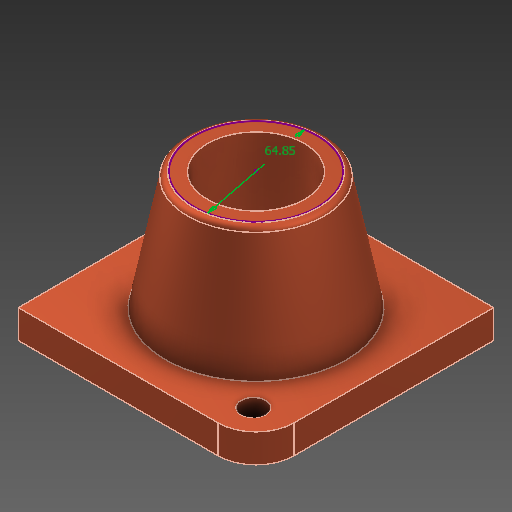
# Autodesk Inventor part: P FLange
Saved by Autodesk Inventor 2026.1 (Build 301233020, 233B)
## iProperties
Created: 2026-10-26
Part Number: P FLange
Material: Copper, Alloy
Document SubType Name: Modeling
Designer: YmCris
Density: 8.92 g/cm^3
Appearance: Copper - Satin
Author: YmCris
Autodesk Inventor part; units mm, degrees
ref_plane "YZ Plane" through (0, 0, 0) normal (1, 0, 0) x (0, 1, 0)
ref_plane "XZ Plane" through (0, 0, 0) normal (0, 1, 0) x (-1, 0, 0)
sketch "Sketch1" plane through (0, 0, 0) normal (0, 1, 0) x (-1, 0, 0)
  line L0 (62.5, 62.5) -> (-42.5, 62.5)
  line L1 (-62.5, 42.5) -> (-62.5, -62.5)
  line L2 (-62.5, -62.5) -> (42.5, -62.5)
  line L3 (62.5, -42.5) -> (62.5, 62.5)
  line L4 (62.5, 62.5) -> (-62.5, -62.5) construction
  line L5 (-62.5, 62.5) -> (62.5, -62.5) construction
  arc A0 (-42.5, 62.5) -> (-62.5, 42.5) centre (-42.5, 42.5) ccw
  arc A1 (42.5, -62.5) -> (62.5, -42.5) centre (42.5, -42.5) ccw
  point P0 (0, 0)
  dimension "d0" = 125
  dimension "d1" = 125
  dimension "d2" = 20
  dimension "d3" = 20
  constraints: 12 end point, 4 point on circle, 4 point on line, 4 tangent, 2 centre point, 2 midpoint, 2 parallel, 1 horizontal, 1 perpendicular
  measures "d0" distance of L5.end L1.end
  measures "d1" distance of L1.end L5.start
  measures "d2" radius of A0
  measures "d3" radius of A1
extrude "Extrusion1" add sketch "Sketch1" along normal blind 15
sketch "Sketch3" plane through (0, 15, 0) normal (0, 1, 0) x (1, 0, 0)
  point P0 (0, 0)
ref_plane "Work Plane1" through (0, 77, 0) normal (0, 1, 0) x (1, 0, 0)
sketch "Sketch4" plane through (0, 77, 0) normal (0, 1, 0) x (1, 0, 0)
  circle A0 centre (0, 0) radius 35.39
  dimension "d10" = 70.78
  constraints: 1 centre point, 1 coincident
  measures "d10" diameter of A0
sketch "Sketch5" plane through (0, 15, 0) normal (0, 1, 0) x (1, 0, 0)
  point P0 (0, 0)
sketch "Sketch6" plane through (0, 15, 0) normal (0, 1, 0) x (1, 0, 0)
  circle A0 centre (0, 0) radius 47.575
  dimension "d11" = 95.15
  constraints: 1 centre point, 1 coincident
  measures "d11" diameter of A0
loft "Loft1" add profiles "Sketch4", "Sketch6"
sketch "Sketch7" plane through (0, 77, 0) normal (0, 1, 0) x (1, 0, 0)
  circle A0 centre (0, 0) radius 25.5
  dimension "d16" = 51
  constraints: 1 centre point, 1 coincident
  measures "d16" diameter of A0
sketch "Sketch8" plane through (0, 77, 0) normal (0, 1, 0) x (1, 0, 0)
  circle A0 centre (0, 0) radius 32.425
  dimension "d17" = 64.85
  constraints: 1 centre point, 1 coincident
  measures "d17" diameter of A0
extrude "Extrusion3" cut sketch "Sketch7" against normal blind 80
fillet "Fillet1" radius 3 1 edges at (-35.39, 77, 0)
sketch "Sketch9" plane through (0, 15, 0) normal (0, 1, 0) x (1, 0, 0)
  circle A0 centre (44.8269, -46.2244) radius 6.5
  circle A1 centre (-44.8269, 46.2244) radius 6.5
  point P0 (0, 0)
  dimension "d21" = 13
  dimension "d24" = 360
  constraints: 2 centre point, 5 other
  measures "d21" diameter of A0
extrude "Extrusion4" cut sketch "Sketch9" against normal blind 15
body "Solid1"
